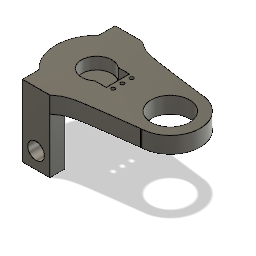
Maintiens engrenages v8 (Autodesk Fusion 360 design; units mm, degrees)
Autodesk Fusion 360 part; units mm, degrees
sketch "Sketch1" plane through (0, 0, 0) normal (0, 1, 0) x (1, 0, 0)
  circle A0 centre (-330.75, 0) radius 8.25
  circle A1 centre (-290.75, 0) radius 16.25
  circle A2 centre (-290.75, 0) radius 10.5
  line L0 (-325.4413, 6.315) -> (-319.3071, 6.315)
  line L1 (-319.3071, 6.315) -> (-319.3071, -6.315)
  line L2 (-319.3071, -6.315) -> (-325.4413, -6.315)
  circle A3 centre (-330.75, 0) radius 16.25
  line L3 (-330.75, -16.25) -> (-290, -16.25)
  line L4 (-330.75, 16.25) -> (-290, 16.25)
  line L5 (-346, -16.25) -> (-346, -20.75)
  line L6 (-331, -20.75) -> (-331, -16.25)
  line L7 (-346, 16.25) -> (-346, 20.75)
  line L8 (-331, 20.75) -> (-331, 16.25)
  line L9 (-346, -17.75) -> (-331, -17.75)
  line L10 (-346, 17.75) -> (-331, 17.75)
  arc A4 (-346, 16.25) -> (-346, -16.25) centre (-330.75, 0) ccw
  line L11 (-331, -16.25) -> (-330.75, -16.25)
  line L12 (-330.75, 16.25) -> (-331, 16.25)
  line L13 (-331, -16.25) -> (-331, -25.25)
  line L14 (-331, -25.25) -> (-346, -25.25)
  line L15 (-346, -25.25) -> (-346, -20.75)
  line L16 (-331, 16.25) -> (-331, 25.25)
  line L17 (-331, 25.25) -> (-346, 25.25)
  line L18 (-346, 25.25) -> (-346, 20.75)
  spline S0 degree 2 poles (-331, 25.25) (-325.4413, 20.75) (-290, 16.25) knots 0 0 0 4.234985 4.234985 4.234985 weights 1 3 1
  spline S1 degree 2 poles (-331, -25.25) (-325.4413, -20.75) (-290, -16.25) knots 0 0 0 4.234985 4.234985 4.234985 weights 1 3 1
  line L19 (-346, 17) -> (-331, 17.0353)
  line L20 (-346, -17) -> (-331, -17.0684)
  circle A5 centre (-316.8071, 0) radius 1
  circle A6 centre (-316.8071, 5) radius 1
  circle A7 centre (-316.8071, -5) radius 1
  point P0 (432.968, 0)
  point P1 (432.968, 0)
  dimension "d3" = 16.5
  dimension "d9" = 32.5
  dimension "d10" = 21
  dimension "d11" = 32.5
  dimension "d33" = 15
  dimension "d46" = 9
  dimension "d47" = 9
  dimension "d53" = 2
  dimension "d55" = 2
  dimension "d57" = 2
  measures "d3" diameter of A0
  measures "d9" diameter of A1
  measures "d10" diameter of A2
  measures "d11" diameter of A3
  measures "d53" diameter of A5
  measures "d55" diameter of A6
  measures "d57" diameter of A7
extrude "Extrude1" add sketch "Sketch1" along normal blind 2.5 contours A0 | A0 L0 L1 L2
extrude "Extrude2" add sketch "Sketch1" along normal blind 9 contours A1 | A1 A3 L3 L4 | A3 L4 L8 L12 L16 S0 | A3 L3 L6 L11 L13 S1 | A3 L11 L12 | A3 L5 L6 L7 L8 A4 L13 L16 L19 L20 | L7 L8 L10 L16 L17 L18 | L5 L6 L9 L13 L14 L15 | L7 L8 L10 L16 L19 | L5 L6 L9 L13 L20 | A5 | A6 | A7
sketch "Sketch2" plane through (0, 0, 20.75) normal (0, 0, 1) x (1, 0, 0)
  circle A0 centre (-338.5, -21) radius 4.5
  point P0 (589825.1328, 0)
  dimension "d39" = 9
  measures "d39" diameter of A0
extrude "Extrude9" add sketch "Sketch1" against normal blind 30 contours L7 L8 L10 L16 L17 L18 | L5 L6 L9 L13 L14 L15 | L7 L8 L10 L16 L19 | L5 L6 L9 L13 L20
extrude "Extrude10" cut sketch "Sketch2" against normal blind 46
extrude "Extrude11" cut sketch "Sketch2" along normal blind 4.5
extrude "Extrude12" cut sketch "Sketch1" along normal blind 9 contours A5 | A6 | A7
